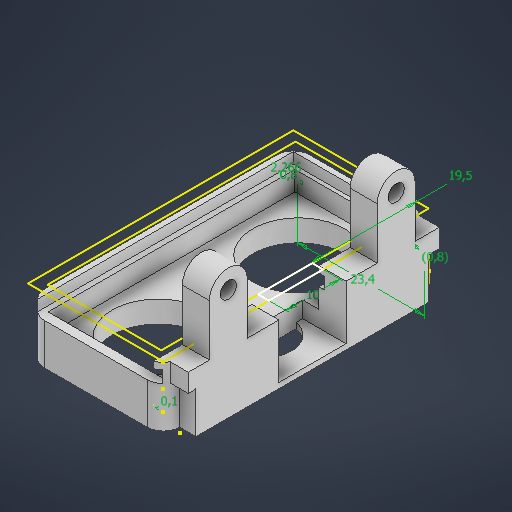
# Autodesk Inventor part: do_oczu
Saved by Autodesk Inventor 2026.1 (Build 301233020, 233B)
## iProperties
Created: 2026-07-31
Part Number: do_oczu
Material: Ogólny
Document SubType Name: Modeling
Designer: Nitro
Density: 1 g/cm^3
Appearance: Domyślna
Author: Nitro
Autodesk Inventor part; units mm, degrees
ref_plane "YZ Plane" through (0, 0, 0) normal (1, 0, 0) x (0, 1, 0)
ref_plane "XZ Plane" through (0, 0, 0) normal (0, 1, 0) x (-1, 0, 0)
ref_plane "XY Plane" through (0, 0, 0) normal (0, 0, 1) x (1, 0, 0)
sketch "Szkic1" plane through (0, 0, 0) normal (0, 1, 0) x (-1, 0, 0)
  line L0 (0, 0) -> (25, 0)
  line L1 (25, 0) -> (25, -49)
  line L2 (25, -49) -> (0, -49)
  line L3 (0, -49) -> (0, 0)
  line L4 (23, -1.6) -> (2, -1.6)
  line L5 (2, -1.6) -> (2, -47.4)
  line L6 (2, -47.4) -> (23, -47.4)
  line L7 (23, -47.4) -> (23, -1.6)
  point P0 (12.5, -1.6)
  dimension "d0" = 45.8
  dimension "d1" = 21
  dimension "d2" = 49
  dimension "d3" = 25
  dimension "d4" = 2
  dimension "d5" = 1.6
  constraints: 16 end point, 4 parallel, 2 horizontal, 2 perpendicular, 1 midpoint
  measures "d0" distance of L4.end L5.end
  measures "d1" distance of L5.end L6.end
  measures "d2" distance of L0.end L1.end
  measures "d3" distance of L1.end L2.end
  measures "d4" distance between parallel lines of L3 L5
  measures "d5" distance from line of L0 point (12.5, -1.6)
extrude "Wyciągnięcie proste1" add sketch "Szkic1" along normal blind 10
sketch "Szkic2" plane through (0, 0, 0) normal (0, -1, 0) x (1, 0, 0)
  line L0 (0, -49) -> (-25, -49) projected
  line L1 (0, 0) -> (0, -49) projected
  line L2 (-25, 0) -> (0, 0) projected
  line L3 (-25, -49) -> (-25, 0) projected
  line L4 (-23, -1.6) -> (-23, -47.4) projected
  line L5 (-2, -1.6) -> (-23, -1.6) projected
  line L6 (-2, -47.4) -> (-2, -1.6) projected
  line L7 (-23, -47.4) -> (-2, -47.4) projected
  line L8 (-25, -49) -> (0, -49)
  line L9 (0, -49) -> (0, 0)
  line L10 (0, 0) -> (-25, 0)
  line L11 (-25, 0) -> (-25, -49)
  constraints: 8 end point, 2 parallel, 1 horizontal, 1 perpendicular
extrude "Wyciągnięcie proste2" add sketch "Szkic2" along normal blind 2 contours L0 L3 L2 L1 | L5 L6 L7 L4
sketch "Szkic3" plane through (0, 0, 0) normal (0, 1, 0) x (1, 0, 0)
  line L0 (-2, 1.6) -> (-23, 1.6) projected
  line L1 (-2, 47.4) -> (-2, 1.6) projected
  line L2 (-23, 47.4) -> (-2, 47.4) projected
  line L3 (-23, 1.6) -> (-23, 47.4) projected
  circle A0 centre (-12.5, 11.5) radius 8.5
  circle A1 centre (-12.5, 37.5) radius 8.5
  point P0 (0, 0)
  dimension "d10" = 17
  dimension "d11" = 17
  dimension "d12" = 26
  dimension "d13" = 9.9
  dimension "d30" = 9.9
  constraints: 2 centre point
  measures "d10" diameter of A1
  measures "d11" diameter of A0
  measures "d12" distance of A1.centre A0.centre
  measures "d13" distance from line of L2 A1.centre
  measures "d30" distance from line of L0 A0.centre
extrude "Wyciągnięcie proste3" cut sketch "Szkic3" against normal blind 2 contours A0 | A1
sketch "Szkic4" plane through (0, 10, 0) normal (0, 1, 0) x (1, 0, 0)
  line L0 (0, 49) -> (-25, 49) projected
  line L1 (-25, 49) -> (-25, 0) projected
  line L2 (-25, 0) -> (0, 0) projected
  line L3 (0, 0) -> (0, 49) projected
  line L4 (-23, 1.6) -> (-23, 47.4) projected
  line L5 (-23, 47.4) -> (-2, 47.4) projected
  line L6 (-2, 47.4) -> (-2, 1.6) projected
  line L7 (-2, 1.6) -> (-23, 1.6) projected
  line L8 (-2, 19.5) -> (0, 19.5)
  line L9 (0, 19.5) -> (0, 29.5)
  line L10 (0, 29.5) -> (-2, 29.5)
  line L11 (-2, 29.5) -> (-2, 19.5)
  dimension "d16" = 10
  dimension "d17" = 19.5
  constraints: 8 end point, 2 parallel, 2 point on line, 1 horizontal, 1 perpendicular
  measures "d16" distance of L9.end L8.end
  measures "d17" distance between parallel lines of L0 L10
sketch "Szkic5" plane through (0, 0, 0) normal (0, 1, 0) x (1, 0, 0)
  circle A0 centre (-12.5, 37.5) radius 8.5 projected
  circle A1 centre (-12.5, 11.5) radius 8.5 projected
  line L0 (-2, 1.6) -> (-23, 1.6) projected
  line L1 (-2, 47.4) -> (-2, 1.6) projected
  line L2 (-23, 47.4) -> (-2, 47.4) projected
  line L3 (-23, 1.6) -> (-23, 47.4) projected
  point P0 (0, 0)
extrude "Wyciągnięcie proste4" add sketch "Szkic5" along normal blind 2
sketch "Szkic6" plane through (0, 10, 0) normal (0, 1, 0) x (1, 0, 0)
  line L0 (0, 49) -> (0, 0) projected
  line L1 (0, 19.5333) -> (-5, 19.5333)
  line L2 (-5, 19.5333) -> (-5, 29.5333)
  line L3 (-5, 29.5333) -> (0, 29.5333)
  line L4 (0, 29.5333) -> (0, 19.5333)
  point P0 (0, 29.5333)
  dimension "d20" = 5
  dimension "d21" = 10
  constraints: 8 end point, 2 parallel, 1 horizontal, 1 perpendicular, 1 point on line
  measures "d20" distance of L2.end L3.end
  measures "d21" distance of L1.end L2.end
extrude "Wyciągnięcie proste5" cut sketch "Szkic6" against normal blind 10.6
sketch "Szkic7" plane through (0, 2, 0) normal (0, 1, 0) x (1, 0, 0)
  point P0 (0, 0)
sketch "Szkic8" plane through (0, 10, -49) normal (0, 0, -1) x (-1, 0, 0)
  point P0 (0, -10)
sketch "Szkic9" plane through (0, 10, 0) normal (0, 1, 0) x (1, 0, 0)
  line L0 (-26.8727, -4.0166) -> (6.0886, -4.0166)
  line L1 (6.0886, -4.0166) -> (6.0886, 61.1411)
  line L2 (6.0886, 61.1411) -> (-26.8727, 61.1411)
  line L3 (-26.8727, 61.1411) -> (-26.8727, -4.0166)
  point P0 (0, 0)
  constraints: 8 end point, 2 parallel, 1 horizontal, 1 perpendicular
extrude "Wyciągnięcie proste6" cut sketch "Szkic9" against normal blind 4
sketch "Szkic10" plane through (0, -2, -49) normal (0, 0, -1) x (-1, 0, 0)
  point P0 (0, 2)
sketch "Szkic11" plane through (0, -2, -49) normal (0, 0, -1) x (-1, 0, 0)
  line L0 (0.8, 6.266) -> (24.2, 6.266)
  line L1 (24.2, 6.266) -> (24.2, 4)
  line L2 (24.2, 4) -> (0.8, 4)
  line L3 (0.8, 4) -> (0.8, 6.266)
  line L4 (25, 0) -> (25, 8) projected
  line L5 (0, 8) -> (0, 0) projected
  point P0 (0, 2)
  dimension "d26" = 23.4
  dimension "d27" = 0.8
  dimension "d28" = 0.8
  dimension "d29" = 2.266
  constraints: 8 end point, 2 parallel, 1 horizontal, 1 perpendicular
  measures "d26" distance of L1.end L2.end
  measures "d27" distance between parallel lines of L4 L1
  measures "d28" distance between parallel lines of L5 L3
  measures "d29" distance between parallel lines of L0 L2
sketch "Szkic12" plane through (0, 6, 0) normal (0, 1, 0) x (1, 0, 0)
  line L0 (-23, 47.4) -> (-23, 1.6) projected
  line L1 (-2, 47.4) -> (-23, 47.4) projected
  line L2 (-2, 29.5333) -> (-2, 47.4) projected
  line L3 (0, 29.5333) -> (-2, 29.5333) projected
  line L4 (0, 49) -> (0, 29.5333) projected
  line L5 (-25, 49) -> (0, 49) projected
  line L6 (-25, 0) -> (-25, 49) projected
  line L7 (0, 0) -> (-25, 0) projected
  line L8 (0, 19.5333) -> (0, 0) projected
  line L9 (-2, 19.5333) -> (0, 19.5333) projected
  line L10 (-2, 1.6) -> (-2, 19.5333) projected
  line L11 (-23, 1.6) -> (-2, 1.6) projected
extrude "Wyciągnięcie proste7" add sketch "Szkic12" along normal blind 4
sketch "Szkic13" plane through (-25, -2, 0) normal (0, 0, 1) x (1, 0, 0)
  line L0 (1, 9.6) -> (24, 9.6)
  line L1 (24, 9.6) -> (24, 7.6)
  line L2 (24, 7.6) -> (1, 7.6)
  line L3 (1, 7.6) -> (1, 9.6)
  line L4 (25, 0) -> (0, 0) projected
  point P0 (25, 2)
  dimension "d33" = 2
  dimension "d34" = 23
  dimension "d35" = 1
  dimension "d36" = 7.6
  constraints: 8 end point, 2 parallel, 1 horizontal, 1 perpendicular
  measures "d33" distance between parallel lines of L0 L2
  measures "d34" distance between parallel lines of L3 L1
  measures "d35" distance from line of point (25, 2) L1
  measures "d36" distance between parallel lines of L4 L2
extrude "Wyciągnięcie proste8" cut sketch "Szkic13" against normal blind 48
sketch "Szkic14" plane through (0, 10, 0) normal (0, 1, 0) x (1, 0, 0)
  line L0 (-2, 47.4) -> (-2, 29.5333) projected
  line L1 (-2, 29.5333) -> (0, 29.5333) projected
  line L2 (0, 29.5333) -> (0, 49) projected
  line L3 (0, 49) -> (-25, 49) projected
  line L4 (-25, 49) -> (-25, 0) projected
  line L5 (-25, 0) -> (0, 0) projected
  line L6 (0, 0) -> (0, 19.5333) projected
  line L7 (0, 19.5333) -> (-2, 19.5333) projected
  line L8 (-2, 19.5333) -> (-2, 1.6) projected
  line L9 (-2, 1.6) -> (-23, 1.6) projected
  line L10 (-23, 1.6) -> (-23, 47.4) projected
  line L11 (-23, 47.4) -> (-2, 47.4) projected
extrude "Wyciągnięcie proste9" cut sketch "Szkic14" against normal blind 1
sketch "Szkic15" plane through (0, -2, 0) normal (1, 0, 0) x (0, 0, -1)
  line L0 (19.5333, 11) -> (0, 11) projected
  line L1 (0, 0) -> (0, 11) projected
  line L2 (49, 0) -> (0, 0) projected
  line L3 (49, 11) -> (49, 0) projected
  line L4 (49, 11) -> (29.5333, 11) projected
  line L5 (29.5333, 11) -> (29.5333, 1.4) projected
  line L6 (29.5333, 1.4) -> (19.5333, 1.4) projected
  line L7 (19.5333, 1.4) -> (19.5333, 11) projected
  line L8 (19.5333, 11) -> (18.1333, 11)
  line L9 (18.1333, 11) -> (18.1333, 0)
  line L10 (18.1333, 0) -> (19.5333, 0)
  line L11 (19.5333, 0) -> (19.5333, 11)
  line L12 (19.5333, 1.4) -> (29.5333, 1.4)
  line L13 (29.5333, 1.4) -> (29.5333, 0)
  line L14 (29.5333, 0) -> (19.5333, 0)
  line L15 (19.5333, 0) -> (19.5333, 1.4)
  line L16 (29.5333, 11) -> (30.9333, 11)
  line L17 (30.9333, 11) -> (30.9333, 0)
  line L18 (30.9333, 0) -> (29.5333, 0)
  line L19 (29.5333, 0) -> (29.5333, 11)
  point P0 (0, 2)
  dimension "d41" = 1.4
  dimension "d42" = 1.4
  constraints: 24 end point, 6 parallel, 3 horizontal, 3 perpendicular, 3 point on line
  measures "d41" distance of L10.end L9.end
  measures "d42" distance of L17.end L18.end
extrude "Wyciągnięcie proste10" add sketch "Szkic15" along normal blind 3 contours L7 L11 L2 L9 L0 | L6 L13 L2 L11 | L5 L4 L17 L2 L13
sketch "Szkic16" plane through (0, -2, -49) normal (1, 0, 0) x (0, 0, -1)
  line L0 (-49, 7.6) -> (-29.4667, 7.6) projected
  line L1 (-29.4667, 4) -> (-47.4, 4) projected
  line L2 (-30.8667, 0) -> (-30.8667, 11) projected
  line L3 (-30.8667, 11) -> (-49, 11) projected
  line L4 (-49, 0) -> (-49, 11) projected
  line L5 (-30.8667, 0) -> (-49, 0) projected
  line L6 (-18.0667, 11) -> (-18.0667, 0) projected
  line L7 (0, 0) -> (-18.0667, 0) projected
  line L8 (0, 11) -> (0, 0) projected
  line L9 (0, 11) -> (-18.0667, 11) projected
  line L10 (-40, 5.5) -> (-40, 20.5) construction
  line L11 (-36.5, 5.5) -> (-36.5, 20.5)
  line L12 (-43.5, 20.5) -> (-43.5, 5.5)
  arc A0 (-43.5, 5.5) -> (-36.5, 5.5) centre (-40, 5.5) ccw
  arc A1 (-36.5, 20.5) -> (-43.5, 20.5) centre (-40, 20.5) ccw
  line L13 (-9, 5.5) -> (-9, 20.5) construction
  line L14 (-5.5, 5.5) -> (-5.5, 20.5)
  line L15 (-12.5, 20.5) -> (-12.5, 5.5)
  arc A2 (-12.5, 5.5) -> (-5.5, 5.5) centre (-9, 5.5) ccw
  arc A3 (-5.5, 20.5) -> (-12.5, 20.5) centre (-9, 20.5) ccw
  point P0 (-49, 2)
  point P1 (-40, 13)
  point P2 (-9, 13)
  dimension "d45" = 15
  dimension "d46" = 7
  dimension "d47" = 7
  dimension "d48" = 9
  dimension "d49" = 9
  dimension "d50" = 31
  dimension "d51" = 5.5
  dimension "d52" = 9.5
  constraints: 16 end point, 8 point on circle, 8 tangent, 4 centre point, 3 parallel, 2 midpoint, 1 vertical
  measures "d45" distance of L10.start L10.end
  measures "d46" diameter of A1
  measures "d47" diameter of A3
  measures "d48" distance from line of L4 L10.start
  measures "d49" distance from line of L8 L13.start
  measures "d50" distance of L13.start L10.start
  measures "d51" distance from line of L7 L13.start
  measures "d52" distance from line of L9 L13.end
extrude "Wyciągnięcie proste11" add sketch "Szkic16" against normal blind 2 contours L12 L3 L11 L0 | L0 L11 A0 L1 L12 | L12 A1 L11 L3 | L1 A0 | L15 A3 L14 L9 | L9 L14 A2 L15
sketch "Szkic17" plane through (-2, 2, -19.5333) normal (-1, 0, 0) x (0, 0, 1)
  line L0 (7.0333, 7) -> (0, 7) projected
  line L1 (0, 7) -> (0, 5.6) projected
  line L2 (0, 5.6) -> (7.0333, 5.6) projected
  line L3 (7.0333, 5.6) -> (7.0333, 3.6) projected
  line L4 (7.0333, 3.6) -> (0, 3.6) projected
  line L5 (0, 3.6) -> (0, 0) projected
  line L6 (0, 0) -> (17.9333, 0) projected
  line L7 (17.9333, 0) -> (17.9333, 3.6) projected
  line L8 (17.9333, 3.6) -> (14.0333, 3.6) projected
  line L9 (14.0333, 3.6) -> (14.0333, 5.6) projected
  line L10 (14.0333, 5.6) -> (17.9333, 5.6) projected
  line L11 (17.9333, 5.6) -> (17.9333, 7) projected
  line L12 (17.9333, 7) -> (14.0333, 7) projected
  line L13 (14.0333, 7) -> (14.0333, 16.5) projected
  arc A0 (14.0333, 16.5) -> (7.0333, 16.5) centre (10.5333, 16.5) ccw projected
  line L14 (7.0333, 16.5) -> (7.0333, 7) projected
  line L15 (-23.9667, 7) -> (-27.8667, 7) projected
  line L16 (-27.8667, 5.6) -> (-27.8667, 7) projected
  line L17 (-27.8667, 5.6) -> (-23.9667, 5.6) projected
  line L18 (-23.9667, 5.6) -> (-23.9667, 3.6) projected
  line L19 (-23.9667, 3.6) -> (-27.8667, 3.6) projected
  line L20 (-27.8667, 0) -> (-27.8667, 3.6) projected
  line L21 (-27.8667, 0) -> (-10, 0) projected
  line L22 (-10, 0) -> (-10, 3.6) projected
  line L23 (-10, 3.6) -> (-16.9667, 3.6) projected
  line L24 (-16.9667, 3.6) -> (-16.9667, 5.6) projected
  line L25 (-16.9667, 5.6) -> (-10, 5.6) projected
  line L26 (-10, 5.6) -> (-10, 7) projected
  line L27 (-10, 7) -> (-16.9667, 7) projected
  line L28 (-16.9667, 7) -> (-16.9667, 16.5) projected
  arc A1 (-16.9667, 16.5) -> (-23.9667, 16.5) centre (-20.4667, 16.5) ccw projected
  line L29 (-23.9667, 16.5) -> (-23.9667, 7) projected
  circle A2 centre (10.5333, 16.5) radius 1.5
  circle A3 centre (-20.4667, 16.5) radius 1.5
  point P0 (19.5333, -2)
  dimension "d55" = 3
  dimension "d56" = 3
  constraints: 2 centre point, 2 coincident
  measures "d55" diameter of A2
  measures "d56" diameter of A3
extrude "Wyciągnięcie proste12" cut sketch "Szkic17" against normal blind 2 contours A2 | A3
sketch "Szkic18" plane through (-1, 5.6, -19.5333) normal (-1, 0, 0) x (0, 0, 1)
  line L0 (17.9333, 0) -> (14.0333, 0) projected
  line L1 (-23.9667, 2) -> (-28.4667, 2) projected
  line L2 (17.9333, 0) -> (-27.0443, 0)
  line L3 (-27.0443, 0) -> (-27.0443, 2)
  line L4 (-27.0443, 2) -> (17.9333, 2)
  line L5 (17.9333, 2) -> (17.9333, 0)
  point P0 (19.5333, -5.6)
  constraints: 8 end point, 2 parallel, 1 horizontal, 1 perpendicular, 1 point on line
extrude "Wyciągnięcie proste13" cut sketch "Szkic18" along normal blind 2
fillet "Zaokrąglenie1" radius 3 4 edges at (-25, 3.5, -49) (-25, 3.5, 0) (0, 3.5, -49) (0, 3.5, 0)
sketch "Szkic19" plane through (0, -2, 0) normal (0, -1, 0) x (1, 0, 0)
  circle A0 centre (-12.5, -11.5) radius 8.5 projected
  circle A1 centre (-12.5, -37.5) radius 8.5 projected
  arc A2 (0, -3) -> (-3, 0) centre (-3, -3) ccw projected
  line L0 (-3, 0) -> (-22, 0) projected
  arc A3 (-22, 0) -> (-25, -3) centre (-22, -3) ccw projected
  line L1 (-25, -3) -> (-25, -46) projected
  arc A4 (-25, -46) -> (-22, -49) centre (-22, -46) ccw projected
  line L2 (-22, -49) -> (-3, -49) projected
  arc A5 (-3, -49) -> (0, -46) centre (-3, -46) ccw projected
  line L3 (0, -46) -> (0, -30.9333) projected
  line L4 (0, -30.9333) -> (3, -30.9333) projected
  line L5 (3, -18.1333) -> (3, -30.9333) projected
  line L6 (0, -18.1333) -> (3, -18.1333) projected
  line L7 (0, -18.1333) -> (0, -3) projected
  line L8 (-5, -19.5333) -> (-5, -29.5333) projected
  arc A6 (-5, -29.5333) -> (-5, -19.5333) centre (-5.9557, -24.5333) ccw
  point P0 (0, 0)
  constraints: 2 point on circle, 1 centre point
extrude "Wyciągnięcie proste14" cut sketch "Szkic19" against normal blind 0.6 contours A6 L8
sketch "Szkic20" plane through (0, -1.4, 0) normal (0, -1, 0) x (1, 0, 0)
  arc A0 (-5, -29.5333) -> (-5, -19.5333) centre (-5.9557, -24.5333) ccw projected
  line L0 (-5, -29.5333) -> (-5, -19.5333) projected
  point P0 (0, 0)
extrude "Wyciągnięcie proste15" cut sketch "Szkic20" against normal blind 12
sketch "Szkic21" plane through (0, 9, 0) normal (0, 1, 0) x (1, 0, 0)
  arc A0 (-3, 0) -> (0, 3) centre (-3, 3) ccw projected
  line L0 (0, 5.5) -> (0, 3) projected
  line L1 (0, 5.5) -> (-2, 5.5) projected
  line L2 (-2, 1.6) -> (-2, 5.5) projected
  line L3 (-23, 1.6) -> (-2, 1.6) projected
  line L4 (-23, 47.4) -> (-23, 1.6) projected
  line L5 (-2, 47.4) -> (-23, 47.4) projected
  line L6 (-2, 43.5) -> (-2, 47.4) projected
  line L7 (-2, 43.5) -> (0, 43.5) projected
  line L8 (0, 46) -> (0, 43.5) projected
  arc A1 (0, 46) -> (-3, 49) centre (-3, 46) ccw projected
  line L9 (-22, 49) -> (-3, 49) projected
  arc A2 (-22, 49) -> (-25, 46) centre (-22, 46) ccw projected
  line L10 (-25, 3) -> (-25, 46) projected
  arc A3 (-25, 3) -> (-22, 0) centre (-22, 3) ccw projected
  line L11 (-3, 0) -> (-22, 0) projected
  line L12 (-27.6859, 50.904) -> (-2, 50.904)
  line L13 (-2, 50.904) -> (-2, -1.7887)
  line L14 (-2, -1.7887) -> (-27.6859, -1.7887)
  line L15 (-27.6859, -1.7887) -> (-27.6859, 50.904)
  point P0 (0, 0)
  constraints: 8 end point, 2 parallel, 1 horizontal, 1 perpendicular
extrude "Wyciągnięcie proste16" cut sketch "Szkic21" against normal blind 1.4 contours L11 A3 L10 A2 L9 A1 L13 L5 L4 L3 A0 | A0 L13 L14 L15 L12 A1 L9 A2 L10 A3 L11 | L3 L4 L5 L6 L13 L2
sketch "Szkic22" plane through (-24, 5.6, -48) normal (0, 1, 0) x (1, 0, 0)
  point P0 (24, -48)
sketch "Szkic23" plane through (-24, 5.6, -48) normal (0, 1, 0) x (1, 0, 0)
  arc A0 (21, -48) -> (23, -47.2361) centre (21, -45) ccw projected
  line L0 (23, -47.2361) -> (23, -28.4667) projected
  line L1 (22, -28.4667) -> (23, -28.4667) projected
  line L2 (22, -46.4) -> (22, -28.4667) projected
  line L3 (1, -46.4) -> (22, -46.4) projected
  line L4 (1, -0.6) -> (1, -46.4) projected
  line L5 (22, -0.6) -> (1, -0.6) projected
  line L6 (22, -18.4667) -> (22, -0.6) projected
  line L7 (23, -18.4667) -> (22, -18.4667) projected
  line L8 (23, -18.4667) -> (23, 0) projected
  line L9 (23, 0) -> (0, 0) projected
  line L10 (0, -47.2361) -> (0, 0) projected
  arc A1 (0, -47.2361) -> (2, -48) centre (2, -45) ccw projected
  line L11 (21, -48) -> (2, -48) projected
  line L12 (23, -47.2361) -> (23, -28.4667) projected
  line L13 (23, -46.4) -> (27, -46.4)
  line L14 (27, -46.4) -> (27, 0)
  line L15 (27, 0) -> (23, 0)
  line L16 (23, 0) -> (23, -46.4)
  point P0 (24, -48)
  dimension "d68" = 4
  constraints: 8 end point, 2 parallel, 2 point on line, 1 horizontal, 1 perpendicular
  measures "d68" distance of L15.end L14.end
extrude "Wyciągnięcie proste17" add sketch "Szkic23" along normal blind 3.4 contours L0 L16 L8 L15 L14 L13
sketch "Szkic24" plane through (3, -2, 0) normal (1, 0, 0) x (0, 0, -1)
  line L0 (0.7639, 9.6) -> (48, 9.6) projected
  line L1 (29.5333, 7.6) -> (29.5333, 1.4) projected
  line L2 (29.5333, 1.4) -> (19.5333, 1.4) projected
  line L3 (19.5333, 1.4) -> (19.5333, 7.6) projected
  line L4 (19.5333, 7.6) -> (29.5333, 7.6) projected
  line L5 (1.6, 11) -> (48, 11) projected
  line L6 (1.6, 7.6) -> (1.6, 11) projected
  line L7 (1.6, 7.6) -> (18.1333, 7.6) projected
  line L8 (18.1333, 7.6) -> (18.1333, 0) projected
  line L9 (18.1333, 0) -> (30.9333, 0) projected
  line L10 (30.9333, 0) -> (30.9333, 7.6) projected
  line L11 (30.9333, 7.6) -> (48, 7.6) projected
  line L12 (48, 7.6) -> (48, 11) projected
  line L13 (29.5333, 4) -> (29.5333, 7.6) projected
  line L14 (29.5333, 7.6) -> (19.5333, 7.6)
  line L15 (19.5333, 7.6) -> (19.5333, 12.1896)
  line L16 (19.5333, 12.1896) -> (29.5333, 12.1896)
  line L17 (29.5333, 12.1896) -> (29.5333, 7.6)
  point P0 (0, 2)
  constraints: 8 end point, 2 parallel, 1 horizontal, 1 perpendicular
extrude "Wyciągnięcie proste18" cut sketch "Szkic24" against normal blind 4 contours L15 L5 L17 L0 | L0 L17 L4 L15 | L15 L16 L17 L5
sketch "Szkic25" plane through (0, 9, -43.5) normal (1, 0, 0) x (0, 0, -1)
  line L0 (-38, 0) -> (-31, 0) projected
  line L1 (-31, 0) -> (-31, 9.5) projected
  arc A0 (-31, 9.5) -> (-38, 9.5) centre (-34.5, 9.5) ccw projected
  line L2 (-38, 9.5) -> (-38, 0) projected
  circle A1 centre (-34.5, 9.5) radius 1.5 projected
  line L3 (-7, 0) -> (0, 0) projected
  line L4 (0, 0) -> (0, 9.5) projected
  arc A2 (0, 9.5) -> (-7, 9.5) centre (-3.5, 9.5) ccw projected
  line L5 (-7, 9.5) -> (-7, 0) projected
  circle A3 centre (-3.5, 9.5) radius 1.5 projected
  point P0 (-43.5, -9)
extrude "Wyciągnięcie proste19" add sketch "Szkic25" along normal blind 3
sketch "Szkic26" plane through (0, 2, 0) normal (0, 1, 0) x (1, 0, 0)
  line L0 (-23, 1.6) -> (-2, 1.6) projected
  line L1 (-2, 5.5) -> (-2, 0.1716) projected
  line L2 (-23, 1.6) -> (-2, 1.6)
  line L3 (-2, 1.6) -> (-2, 1.5)
  line L4 (-2, 1.5) -> (-23, 1.5)
  line L5 (-23, 1.5) -> (-23, 1.6)
  point P0 (0, 0)
  dimension "d75" = 0.1
  constraints: 8 end point, 2 parallel, 1 horizontal, 1 perpendicular, 1 point on line
  measures "d75" distance of L2.end L3.end
sketch "Szkic27" plane through (0, 2, 0) normal (0, 1, 0) x (1, 0, 0)
  circle A0 centre (-12.5, 37.5) radius 8.5 projected
  circle A1 centre (-12.5, 11.5) radius 8.5 projected
  line L0 (-2, 19.5333) -> (-5, 19.5333) projected
  line L1 (-5, 19.5333) -> (-5, 29.5333) projected
  line L2 (-5, 29.5333) -> (-2, 29.5333) projected
  line L3 (-2, 47.4) -> (-2, 29.5333) projected
  line L4 (-23, 47.4) -> (-2, 47.4) projected
  line L5 (-23, 1.6) -> (-23, 47.4) projected
  line L6 (-2, 1.6) -> (-23, 1.6) projected
  line L7 (-2, 19.5333) -> (-2, 1.6) projected
  line L8 (-23, 1.7) -> (-2, 1.7)
  line L9 (-2, 1.7) -> (-2, 47.3)
  line L10 (-2, 47.3) -> (-23, 47.3)
  line L11 (-23, 47.3) -> (-23, 1.7)
  line L12 (-23, 1.6) -> (-2, 1.6) projected
  point P0 (0, 0)
  point P1 (-12.5, 1.6)
  point P2 (-2, 1.7)
  dimension "d76" = 0.1
  dimension "d77" = 0.1
  constraints: 8 end point, 2 parallel, 2 point on line, 1 horizontal, 1 midpoint, 1 perpendicular
  measures "d76" distance from line of point (-12.5, 1.6) L8
  measures "d77" distance between parallel lines of L4 L10
extrude "Wyciągnięcie proste20" add sketch "Szkic27" along normal blind 3.6 contours L7 L6 L5 L8 | L10 L5 L4 L3
sketch "Szkic28" plane through (3, -2, 0) normal (1, 0, 0) x (0, 0, -1)
  point P0 (0, 2)
sketch "Szkic29" plane through (0, -2, -30.9333) normal (1, 0, 0) x (0, 0, -1)
  line L0 (-11.4, 4) -> (-29.2333, 4) projected
  line L1 (-12.8, 7.6) -> (-27.9333, 7.6) projected
  line L2 (-27.9333, 0) -> (-27.9333, 7.6) projected
  line L3 (-12.8, 0) -> (-27.9333, 0) projected
  line L4 (-12.8, 0) -> (-12.8, 7.6) projected
  line L5 (15.0667, 7.6) -> (0, 7.6) projected
  line L6 (0, 7.6) -> (0, 0) projected
  line L7 (15.0667, 0) -> (0, 0) projected
  line L8 (15.0667, 7.6) -> (15.0667, 0) projected
  point P0 (-30.9333, 2)
extrude "Wyciągnięcie proste21" add sketch "Szkic29" along normal blind 3
sketch "Szkic30" plane through (-2, 7.6, -29.5333) normal (-1, 0, 0) x (0, 0, 1)
  line L0 (24.0333, 1.4) -> (24.0333, 10.9) projected
  arc A0 (24.0333, 10.9) -> (17.0333, 10.9) centre (20.5333, 10.9) ccw projected
  line L1 (17.0333, 10.9) -> (17.0333, 1.4) projected
  line L2 (17.0333, 1.4) -> (10, 1.4) projected
  line L3 (10, 1.4) -> (10, 0) projected
  line L4 (29.3617, 0) -> (10, 0) projected
  line L5 (29.3617, 1.4) -> (29.3617, 0) projected
  line L6 (24.0333, 1.4) -> (29.3617, 1.4) projected
  circle A1 centre (20.5333, 10.9) radius 1.5 projected
  line L7 (-6.9667, 1.4) -> (-6.9667, 10.9) projected
  arc A2 (-6.9667, 10.9) -> (-13.9667, 10.9) centre (-10.4667, 10.9) ccw projected
  line L8 (-13.9667, 10.9) -> (-13.9667, 1.4) projected
  line L9 (-13.9667, 1.4) -> (-19.2951, 1.4) projected
  line L10 (-19.2951, 0) -> (-19.2951, 1.4) projected
  line L11 (-19.2951, 0) -> (-18.4667, 0) projected
  line L12 (-18.4667, 0) -> (0, 0) projected
  line L13 (0, 0) -> (0, 1.4) projected
  line L14 (0, 1.4) -> (-6.9667, 1.4) projected
  circle A3 centre (-10.4667, 10.9) radius 1.5 projected
  line L15 (29.3617, 1.4) -> (29.3617, 0) projected
  line L16 (29.3617, 0) -> (-18.4667, 0)
  line L17 (-18.4667, 0) -> (-18.4667, 0.2)
  line L18 (-18.4667, 0.2) -> (29.3617, 0.2)
  line L19 (29.3617, 0.2) -> (29.3617, 0)
  point P0 (29.5333, -7.6)
  point P1 (29.3617, 0.2)
  dimension "d82" = 0.2
  constraints: 8 end point, 2 parallel, 1 horizontal, 1 perpendicular
  measures "d82" distance of L16.end L17.end
extrude "Wyciągnięcie proste22" cut sketch "Szkic30" against normal blind 1 contours L5 L4 L3 L18 | L3 L16 L13 L18 | L13 L12 L17 L18
sketch "Szkic31" plane through (0, 9, 0) normal (0, 1, 0) x (1, 0, 0)
  line L0 (-2, 12.5) -> (3, 12.5) projected
  line L1 (3, 12.5) -> (3, 19.5333) projected
  line L2 (-2, 19.5333) -> (3, 19.5333) projected
  line L3 (-2, 12.5) -> (-2, 19.5333) projected
  line L4 (3, 36.5) -> (-2, 36.5) projected
  line L5 (-2, 29.5333) -> (-2, 36.5) projected
  line L6 (3, 29.5333) -> (-2, 29.5333) projected
  line L7 (3, 29.5333) -> (3, 36.5) projected
  line L8 (3, 18.3333) -> (-5, 18.3333)
  line L9 (-5, 18.3333) -> (-5, 30.7333)
  line L10 (-5, 30.7333) -> (3, 30.7333)
  line L11 (3, 30.7333) -> (3, 18.3333)
  point P0 (0, 0)
  point P1 (3, 30.7333)
  dimension "d85" = 1.2
  dimension "d86" = 1.2
  constraints: 8 end point, 2 parallel, 1 horizontal, 1 perpendicular, 1 point on line
  measures "d85" distance between parallel lines of L2 L8
  measures "d86" distance between parallel lines of L6 L10
extrude "Wyciągnięcie proste23" cut sketch "Szkic31" against normal blind 10 contours L8 L9 L10 L5 L6 L11 L2 L3 | L3 L2 L1 L8 | L6 L5 L10 L7
